Foot_pin_v3 (Autodesk Fusion 360 design; units mm, degrees)
Autodesk Fusion 360 part; units mm, degrees
sketch "Sketch1" plane through (0, 0, 0) normal (1, 0, 0) x (0, 1, 0)
  circle A0 centre (0, 0) radius 4
  circle A1 centre (0, 0) radius 3
  dimension "d1" = 8
  dimension "d2" = 6
  constraint coincident A0.centre A1.centre
  measures "d1" diameter of A0
  measures "d2" diameter of A1
extrude "Extrude1" add sketch "Sketch1" along normal blind 55 contours A0 | A1
extrude "Extrude2" cut sketch "Sketch1" along normal blind 54
extrude "Extrude3" add sketch "Sketch1" along normal blind 53
extrude "Extrude4" cut sketch "Sketch1" along normal blind 2
extrude "Extrude5" add sketch "Sketch1" along normal blind 1
chamfer "Chamfer1" distance 1 angle 45 2 edges at (2, -3.7293, -1.4465) (53, -3.7293, -1.4465) tangent chain off
